Autodesk Fusion 360 part; units mm, degrees
(part 3 of 3)
equation "d3462 = ( wall_z0 + fr_w ) - ( wall_z0 )"
equation "d3464 = fr_t"
equation "d3465 = ( fr_z2 ) - ( wall_z0 )"
equation "d3471 = ( fr_z2 ) - ( wall_z0 )"
equation "d3477 = sk_ref"
equation "d3478 = sk_ref"
equation "d3479 = ( ( ( dl_y1 * ( dl_x2 / dl_l1 ) - ( -( ( ( dl_y2 - dl_y1 ) / dl_l1 * ( -pod_w / 2 ) + dl_x2 / dl_l1 * ( -dl_y1 ) + dl_fo ) ) ) ) / ( -( -( ( dl_y2 - dl_y1 ) / dl_l1 ) ) ) ) ) + sk_ref"
equation "d3480 = ( ( ( ( ( ( dl_y2 - dl_y1 ) / dl_l1 * ( -pod_w / 2 ) + dl_x2 / dl_l1 * ( -dl_y1 ) + dl_fo ) ) * ( ( dl_x3 - dl_x2 ) / dl_l2 ) - ( ( ( ( dl_y3 - dl_y2 ) / dl_l2 * ( -pod_w / 2 + dl_x2 ) + ( dl_x3 - dl_x2 ) / dl_l2 * ( -dl_y2 ) + dl_fo ) ) * ( dl_x2 / dl_l1 ) ) ) / ( ( ( dl_y2 - dl_y1 ) / dl_l1 ) * ( ( dl_x3 - dl_x2 ) / dl_l2 ) - ( ( ( dl_y3 - dl_y2 ) / dl_l2 ) * ( dl_x2 / dl_l1 ) ) ) ) ) + sk_ref"
equation "d3481 = ( ( ( ( ( ( dl_y2 - dl_y1 ) / dl_l1 * ( -pod_w / 2 ) + dl_x2 / dl_l1 * ( -dl_y1 ) + dl_fo + fr_w ) ) * ( ( dl_x3 - dl_x2 ) / dl_l2 ) - ( ( ( ( dl_y3 - dl_y2 ) / dl_l2 * ( -pod_w / 2 + dl_x2 ) + ( dl_x3 - dl_x2 ) / dl_l2 * ( -dl_y2 ) + dl_fo + fr_w ) ) * ( dl_x2 / dl_l1 ) ) ) / ( ( ( dl_y2 - dl_y1 ) / dl_l1 ) * ( ( dl_x3 - dl_x2 ) / dl_l2 ) - ( ( ( dl_y3 - dl_y2 ) / dl_l2 ) * ( dl_x2 / dl_l1 ) ) ) ) ) + sk_ref"
equation "d3482 = ( ( ( ( ( dl_y1 + fr_w ) ) * ( dl_x2 / dl_l1 ) - ( -( ( ( dl_y2 - dl_y1 ) / dl_l1 * ( -pod_w / 2 ) + dl_x2 / dl_l1 * ( -dl_y1 ) + dl_fo + fr_w ) ) ) ) / ( -( -( ( dl_y2 - dl_y1 ) / dl_l1 ) ) ) ) ) + sk_ref"
equation "d3483 = ( ( ( -( ( ( dl_y2 - dl_y1 ) / dl_l1 ) * dl_y1 ) ) / ( -( -( ( dl_y2 - dl_y1 ) / dl_l1 ) ) ) ) ) + sk_ref"
equation "d3484 = ( ( ( ( ( dl_y2 - dl_y1 ) / dl_l1 ) * ( ( ( dl_y3 - dl_y2 ) / dl_l2 * ( -pod_w / 2 + dl_x2 ) + ( dl_x3 - dl_x2 ) / dl_l2 * ( -dl_y2 ) + dl_fo ) ) - ( ( ( dl_y3 - dl_y2 ) / dl_l2 ) * ( ( ( dl_y2 - dl_y1 ) / dl_l1 * ( -pod_w / 2 ) + dl_x2 / dl_l1 * ( -dl_y1 ) + dl_fo ) ) ) ) / ( ( ( dl_y2 - dl_y1 ) / dl_l1 ) * ( ( dl_x3 - dl_x2 ) / dl_l2 ) - ( ( ( dl_y3 - dl_y2 ) / dl_l2 ) * ( dl_x2 / dl_l1 ) ) ) ) ) + sk_ref"
equation "d3485 = ( ( ( ( ( dl_y2 - dl_y1 ) / dl_l1 ) * ( ( ( dl_y3 - dl_y2 ) / dl_l2 * ( -pod_w / 2 + dl_x2 ) + ( dl_x3 - dl_x2 ) / dl_l2 * ( -dl_y2 ) + dl_fo + fr_w ) ) - ( ( ( dl_y3 - dl_y2 ) / dl_l2 ) * ( ( ( dl_y2 - dl_y1 ) / dl_l1 * ( -pod_w / 2 ) + dl_x2 / dl_l1 * ( -dl_y1 ) + dl_fo + fr_w ) ) ) ) / ( ( ( dl_y2 - dl_y1 ) / dl_l1 ) * ( ( dl_x3 - dl_x2 ) / dl_l2 ) - ( ( ( dl_y3 - dl_y2 ) / dl_l2 ) * ( dl_x2 / dl_l1 ) ) ) ) ) + sk_ref"
equation "d3486 = ( ( ( -( ( ( dl_y2 - dl_y1 ) / dl_l1 ) * ( ( dl_y1 + fr_w ) ) ) ) / ( -( -( ( dl_y2 - dl_y1 ) / dl_l1 ) ) ) ) ) + sk_ref"
equation "d3487 = ( fr_z2 ) * ( 1 )"
equation "d3488 = ( fr_z2 + fr_w ) - ( fr_z2 )"
equation "d3490 = fr_t"
equation "d3491 = sk_ref"
equation "d3492 = sk_ref"
equation "d3493 = ( ( ( ( ( ( dl_y2 - dl_y1 ) / dl_l1 * ( -pod_w / 2 ) + dl_x2 / dl_l1 * ( -dl_y1 ) + dl_fo ) ) * ( ( dl_x3 - dl_x2 ) / dl_l2 ) - ( ( ( ( dl_y3 - dl_y2 ) / dl_l2 * ( -pod_w / 2 + dl_x2 ) + ( dl_x3 - dl_x2 ) / dl_l2 * ( -dl_y2 ) + dl_fo ) ) * ( dl_x2 / dl_l1 ) ) ) / ( ( ( dl_y2 - dl_y1 ) / dl_l1 ) * ( ( dl_x3 - dl_x2 ) / dl_l2 ) - ( ( ( dl_y3 - dl_y2 ) / dl_l2 ) * ( dl_x2 / dl_l1 ) ) ) ) ) + sk_ref"
equation "d3494 = ( ( ( -( ( ( -( -pod_w / 2 + dl_w ) + dl_fo + fr_w ) ) * ( ( dl_x3 - dl_x2 ) / dl_l2 ) ) ) / ( -( -( ( dl_x3 - dl_x2 ) / dl_l2 ) ) ) ) ) + sk_ref"
equation "d3495 = ( ( ( ( ( ( dl_y2 - dl_y1 ) / dl_l1 * ( -pod_w / 2 ) + dl_x2 / dl_l1 * ( -dl_y1 ) + dl_fo + fr_w ) ) * ( ( dl_x3 - dl_x2 ) / dl_l2 ) - ( ( ( ( dl_y3 - dl_y2 ) / dl_l2 * ( -pod_w / 2 + dl_x2 ) + ( dl_x3 - dl_x2 ) / dl_l2 * ( -dl_y2 ) + dl_fo + fr_w ) ) * ( dl_x2 / dl_l1 ) ) ) / ( ( ( dl_y2 - dl_y1 ) / dl_l1 ) * ( ( dl_x3 - dl_x2 ) / dl_l2 ) - ( ( ( dl_y3 - dl_y2 ) / dl_l2 ) * ( dl_x2 / dl_l1 ) ) ) ) ) + sk_ref"
equation "d3496 = ( ( ( ( ( dl_y2 - dl_y1 ) / dl_l1 ) * ( ( ( dl_y3 - dl_y2 ) / dl_l2 * ( -pod_w / 2 + dl_x2 ) + ( dl_x3 - dl_x2 ) / dl_l2 * ( -dl_y2 ) + dl_fo ) ) - ( ( ( dl_y3 - dl_y2 ) / dl_l2 ) * ( ( ( dl_y2 - dl_y1 ) / dl_l1 * ( -pod_w / 2 ) + dl_x2 / dl_l1 * ( -dl_y1 ) + dl_fo ) ) ) ) / ( ( ( dl_y2 - dl_y1 ) / dl_l1 ) * ( ( dl_x3 - dl_x2 ) / dl_l2 ) - ( ( ( dl_y3 - dl_y2 ) / dl_l2 ) * ( dl_x2 / dl_l1 ) ) ) ) ) + sk_ref"
equation "d3497 = ( ( ( ( ( dl_y3 - dl_y2 ) / dl_l2 ) * ( ( -( -pod_w / 2 + dl_w ) + dl_fo + fr_w ) ) - ( -( ( ( dl_y3 - dl_y2 ) / dl_l2 * ( -pod_w / 2 + dl_x2 ) + ( dl_x3 - dl_x2 ) / dl_l2 * ( -dl_y2 ) + dl_fo ) ) ) ) / ( -( -( ( dl_x3 - dl_x2 ) / dl_l2 ) ) ) ) ) + sk_ref"
equation "d3498 = ( ( ( ( ( dl_y3 - dl_y2 ) / dl_l2 ) * ( ( -( -pod_w / 2 + dl_w ) + dl_fo + fr_w ) ) - ( -( ( ( dl_y3 - dl_y2 ) / dl_l2 * ( -pod_w / 2 + dl_x2 ) + ( dl_x3 - dl_x2 ) / dl_l2 * ( -dl_y2 ) + dl_fo + fr_w ) ) ) ) / ( -( -( ( dl_x3 - dl_x2 ) / dl_l2 ) ) ) ) ) + sk_ref"
equation "d3499 = ( ( ( ( ( dl_y2 - dl_y1 ) / dl_l1 ) * ( ( ( dl_y3 - dl_y2 ) / dl_l2 * ( -pod_w / 2 + dl_x2 ) + ( dl_x3 - dl_x2 ) / dl_l2 * ( -dl_y2 ) + dl_fo + fr_w ) ) - ( ( ( dl_y3 - dl_y2 ) / dl_l2 ) * ( ( ( dl_y2 - dl_y1 ) / dl_l1 * ( -pod_w / 2 ) + dl_x2 / dl_l1 * ( -dl_y1 ) + dl_fo + fr_w ) ) ) ) / ( ( ( dl_y2 - dl_y1 ) / dl_l1 ) * ( ( dl_x3 - dl_x2 ) / dl_l2 ) - ( ( ( dl_y3 - dl_y2 ) / dl_l2 ) * ( dl_x2 / dl_l1 ) ) ) ) ) + sk_ref"
equation "d3500 = ( fr_z2 ) * ( 1 )"
equation "d3501 = ( fr_z2 + fr_w ) - ( fr_z2 )"
equation "d3503 = fr_t"
equation "d3504 = ( fr_z3 ) - ( wall_z0 )"
equation "d3510 = ( fr_z3 ) - ( wall_z0 )"
equation "d3516 = ( fr_z3 ) - ( fr_z2 )"
equation "d3522 = ( fr_z3 ) - ( fr_z2 )"
equation "d3528 = ( fr_z4 ) - ( wall_z0 )"
equation "d3534 = ( fr_z4 ) - ( wall_z0 )"
equation "d3540 = ( fr_z4 ) - ( fr_z2 )"
equation "d3546 = ( fr_z4 ) - ( fr_z2 )"
equation "d3552 = sk_ref"
equation "d3553 = sk_ref"
equation "d3554 = ( ( hinge_x0 - hinge_clear ) ) + sk_ref"
equation "d3555 = ( ( hinge_x0 - hinge_clear ) - fr_w ) + sk_ref"
equation "d3556 = ( -glass_y - fr_wh / 2 ) + sk_ref"
equation "d3557 = ( -glass_y + fr_wh / 2 ) + sk_ref"
equation "d3558 = ( wall_z0 + fr_w ) * ( 1 )"
equation "d3559 = ( fr_z2 ) - ( wall_z0 + fr_w )"
equation "d3561 = fr_t"
equation "d3562 = sk_ref"
equation "d3563 = sk_ref"
equation "d3564 = ( ( ( -( ( ( -( -pod_w / 2 + dl_w ) + dl_fo + fr_w ) ) * ( ( dl_x3 - dl_x2 ) / dl_l2 ) ) ) / ( -( -( ( dl_x3 - dl_x2 ) / dl_l2 ) ) ) ) ) + sk_ref"
equation "d3565 = ( ( -( ( -( -pod_w / 2 + dl_w ) + dl_fo ) ) ) ) + sk_ref"
equation "d3566 = ( ( -( -( ( ( ( ( dl_y3 - dl_y2 ) / dl_l2 ) * ( ( -( -pod_w / 2 + dl_w ) + dl_fo + fr_w ) ) - ( -( ( ( dl_y3 - dl_y2 ) / dl_l2 * ( -pod_w / 2 + dl_x2 ) + ( dl_x3 - dl_x2 ) / dl_l2 * ( -dl_y2 ) + dl_fo ) ) ) ) / ( -( -( ( dl_x3 - dl_x2 ) / dl_l2 ) ) ) ) ) ) ) ) + sk_ref"
equation "d3567 = ( ( -( -( ( ( ( ( dl_y3 - dl_y2 ) / dl_l2 ) * ( ( -( -pod_w / 2 + dl_w ) + dl_fo + fr_w ) ) - ( -( ( ( dl_y3 - dl_y2 ) / dl_l2 * ( -pod_w / 2 + dl_x2 ) + ( dl_x3 - dl_x2 ) / dl_l2 * ( -dl_y2 ) + dl_fo ) ) ) ) / ( -( -( ( dl_x3 - dl_x2 ) / dl_l2 ) ) ) ) + fr_w ) ) ) ) + sk_ref"
equation "d3568 = ( wall_z0 + fr_w ) * ( 1 )"
equation "d3569 = ( fr_z2 ) - ( wall_z0 + fr_w )"
equation "d3571 = fr_t"
equation "d3572 = sk_ref"
equation "d3573 = sk_ref"
equation "d3574 = ( ( hinge_x0 - hinge_clear ) ) + sk_ref"
equation "d3575 = ( ( hinge_x0 - hinge_clear ) - fr_w ) + sk_ref"
equation "d3576 = ( -glass_y - fr_wh / 2 ) + sk_ref"
equation "d3577 = ( -glass_y + fr_wh / 2 ) + sk_ref"
equation "d3578 = ( fr_z2 + fr_w ) * ( 1 )"
equation "d3579 = ( fr_z3 ) - ( fr_z2 + fr_w )"
equation "d3581 = fr_t"
equation "d3582 = sk_ref"
equation "d3583 = sk_ref"
equation "d3584 = ( ( ( -( ( ( -( -pod_w / 2 + dl_w ) + dl_fo + fr_w ) ) * ( ( dl_x3 - dl_x2 ) / dl_l2 ) ) ) / ( -( -( ( dl_x3 - dl_x2 ) / dl_l2 ) ) ) ) ) + sk_ref"
equation "d3585 = ( ( -( ( -( -pod_w / 2 + dl_w ) + dl_fo ) ) ) ) + sk_ref"
equation "d3586 = ( ( -( -( ( ( ( ( dl_y3 - dl_y2 ) / dl_l2 ) * ( ( -( -pod_w / 2 + dl_w ) + dl_fo + fr_w ) ) - ( -( ( ( dl_y3 - dl_y2 ) / dl_l2 * ( -pod_w / 2 + dl_x2 ) + ( dl_x3 - dl_x2 ) / dl_l2 * ( -dl_y2 ) + dl_fo ) ) ) ) / ( -( -( ( dl_x3 - dl_x2 ) / dl_l2 ) ) ) ) ) ) ) ) + sk_ref"
equation "d3587 = ( ( -( -( ( ( ( ( dl_y3 - dl_y2 ) / dl_l2 ) * ( ( -( -pod_w / 2 + dl_w ) + dl_fo + fr_w ) ) - ( -( ( ( dl_y3 - dl_y2 ) / dl_l2 * ( -pod_w / 2 + dl_x2 ) + ( dl_x3 - dl_x2 ) / dl_l2 * ( -dl_y2 ) + dl_fo ) ) ) ) / ( -( -( ( dl_x3 - dl_x2 ) / dl_l2 ) ) ) ) + fr_w ) ) ) ) + sk_ref"
equation "d3588 = ( fr_z2 + fr_w ) * ( 1 )"
equation "d3589 = ( fr_z3 ) - ( fr_z2 + fr_w )"
equation "d3591 = fr_t"
equation "d3592 = sk_ref"
equation "d3593 = sk_ref"
equation "d3594 = ( ( hinge_x0 - hinge_clear ) ) + sk_ref"
equation "d3595 = ( ( hinge_x0 - hinge_clear ) - fr_w ) + sk_ref"
equation "d3596 = ( -glass_y - fr_wh / 2 ) + sk_ref"
equation "d3597 = ( -glass_y + fr_wh / 2 ) + sk_ref"
equation "d3598 = ( fr_z3 + fr_w ) * ( 1 )"
equation "d3599 = ( fr_z4 ) - ( fr_z3 + fr_w )"
equation "d3601 = fr_t"
equation "d3602 = sk_ref"
equation "d3603 = sk_ref"
equation "d3604 = ( ( ( -( ( ( -( -pod_w / 2 + dl_w ) + dl_fo + fr_w ) ) * ( ( dl_x3 - dl_x2 ) / dl_l2 ) ) ) / ( -( -( ( dl_x3 - dl_x2 ) / dl_l2 ) ) ) ) ) + sk_ref"
equation "d3605 = ( ( -( ( -( -pod_w / 2 + dl_w ) + dl_fo ) ) ) ) + sk_ref"
equation "d3606 = ( ( -( -( ( ( ( ( dl_y3 - dl_y2 ) / dl_l2 ) * ( ( -( -pod_w / 2 + dl_w ) + dl_fo + fr_w ) ) - ( -( ( ( dl_y3 - dl_y2 ) / dl_l2 * ( -pod_w / 2 + dl_x2 ) + ( dl_x3 - dl_x2 ) / dl_l2 * ( -dl_y2 ) + dl_fo ) ) ) ) / ( -( -( ( dl_x3 - dl_x2 ) / dl_l2 ) ) ) ) ) ) ) ) + sk_ref"
equation "d3607 = ( ( -( -( ( ( ( ( dl_y3 - dl_y2 ) / dl_l2 ) * ( ( -( -pod_w / 2 + dl_w ) + dl_fo + fr_w ) ) - ( -( ( ( dl_y3 - dl_y2 ) / dl_l2 * ( -pod_w / 2 + dl_x2 ) + ( dl_x3 - dl_x2 ) / dl_l2 * ( -dl_y2 ) + dl_fo ) ) ) ) / ( -( -( ( dl_x3 - dl_x2 ) / dl_l2 ) ) ) ) + fr_w ) ) ) ) + sk_ref"
equation "d3608 = ( fr_z3 + fr_w ) * ( 1 )"
equation "d3609 = ( fr_z4 ) - ( fr_z3 + fr_w )"
equation "d3611 = fr_t"
equation "d3612 = sk_ref"
equation "d3613 = sk_ref"
equation "d3614 = ( -jf_x ) + sk_ref"
equation "d3615 = ( jf_z1 ) + sk_ref"
equation "d3616 = fr_hole_jf"
equation "d3617 = ( -jf_x ) + sk_ref"
equation "d3618 = ( jf_z2 ) + sk_ref"
equation "d3619 = fr_hole_jf"
equation "d3620 = ( -jf_x ) + sk_ref"
equation "d3621 = ( jf_z3 ) + sk_ref"
equation "d3622 = fr_hole_jf"
equation "d3623 = ( -jf_x ) + sk_ref"
equation "d3624 = ( jf_z4 ) + sk_ref"
equation "d3625 = fr_hole_jf"
equation "d3626 = ( -jf_x ) + sk_ref"
equation "d3627 = ( jf_z5 ) + sk_ref"
equation "d3628 = fr_hole_jf"
equation "d3629 = ( -jf_x ) + sk_ref"
equation "d3630 = ( jf_z6 ) + sk_ref"
equation "d3631 = fr_hole_jf"
equation "d3632 = ( -pod_d / 2 + decor_d - dl_back_t - fr_t - 1 mm ) * ( 1 )"
equation "d3633 = ( -pod_d / 2 + decor_d - dl_back_t + 0.5 mm ) - ( -pod_d / 2 + decor_d - dl_back_t - fr_t - 1 mm )"
equation "d3635 = sk_ref"
equation "d3636 = sk_ref"
equation "d3637 = ( sp_ax ) + sk_ref"
equation "d3638 = ( sp_ay ) + sk_ref"
equation "d3639 = sp_hole"
equation "d3640 = ( wall_z0 - 1 mm ) * ( 1 )"
equation "d3641 = ( wall_z0 + fr_t + 0.5 mm ) - ( wall_z0 - 1 mm )"
equation "d3643 = sk_ref"
equation "d3644 = sk_ref"
equation "d3645 = ( sp_bx - ( ( sp_slot - sp_hole ) / 2 ) * sp_d2x ) + sk_ref"
equation "d3646 = ( sp_by - ( ( sp_slot - sp_hole ) / 2 ) * sp_d2y ) + sk_ref"
equation "d3647 = sp_hole"
equation "d3648 = ( sp_bx + ( ( sp_slot - sp_hole ) / 2 ) * sp_d2x ) + sk_ref"
equation "d3649 = ( sp_by + ( ( sp_slot - sp_hole ) / 2 ) * sp_d2y ) + sk_ref"
equation "d3650 = sp_hole"
equation "d3651 = ( wall_z0 - 1 mm ) * ( 1 )"
equation "d3652 = ( wall_z0 + fr_t + 0.5 mm ) - ( wall_z0 - 1 mm )"
equation "d3654 = sk_ref"
equation "d3655 = sk_ref"
equation "d3656 = ( sp_bx - ( ( sp_slot - sp_hole ) / 2 ) * sp_d2x - ( sp_hole / 2 ) * sp_n2x ) + sk_ref"
equation "d3657 = ( sp_bx + ( ( sp_slot - sp_hole ) / 2 ) * sp_d2x - ( sp_hole / 2 ) * sp_n2x ) + sk_ref"
equation "d3658 = ( sp_bx + ( ( sp_slot - sp_hole ) / 2 ) * sp_d2x + ( sp_hole / 2 ) * sp_n2x ) + sk_ref"
equation "d3659 = ( sp_bx - ( ( sp_slot - sp_hole ) / 2 ) * sp_d2x + ( sp_hole / 2 ) * sp_n2x ) + sk_ref"
equation "d3660 = ( sp_by - ( ( sp_slot - sp_hole ) / 2 ) * sp_d2y - ( sp_hole / 2 ) * sp_n2y ) + sk_ref"
equation "d3661 = ( sp_by + ( ( sp_slot - sp_hole ) / 2 ) * sp_d2y - ( sp_hole / 2 ) * sp_n2y ) + sk_ref"
equation "d3662 = ( sp_by + ( ( sp_slot - sp_hole ) / 2 ) * sp_d2y + ( sp_hole / 2 ) * sp_n2y ) + sk_ref"
equation "d3663 = ( sp_by - ( ( sp_slot - sp_hole ) / 2 ) * sp_d2y + ( sp_hole / 2 ) * sp_n2y ) + sk_ref"
equation "d3664 = ( wall_z0 - 1 mm ) * ( 1 )"
equation "d3665 = ( wall_z0 + fr_t + 0.5 mm ) - ( wall_z0 - 1 mm )"
named bodies: "DL SKIN ACP 3", "DL BACK PLATE AL 2", "HINGE-SIDE STOP 1 (ANGLE, BONDED)", "HINGE-SIDE STOP 2 AND 3 (ANGLE, BONDED)", "HINGE-SIDE STOP 4 (ANGLE, BONDED)", "FRAME-STOP SEAL PS 1515 - HINGE SIDE 1", "FRAME-STOP SEAL PS 1515 - HINGE SIDE 2 AND 3", "FRAME-STOP SEAL PS 1515 - HINGE SIDE 4", "B01 BACK RING BOTTOM 20 x 20 x 1.5", "B02 BACK RING DOOR SIDE 20 x 20 x 1.5", "B03 BACK RING SLOPE UNDER DT 20 x 20 x 1.5", "B04 BACK RING BOLT LINE 60 x 20 x 1.5", "R1D RING BOTTOM - DOOR SIDE 20 x 20 x 1.5", "R1K RING BOTTOM - BACK 20 x 20 x 1.5", "R1O RING BOTTOM - OUTER FACET 20 x 20 x 1.5", "R1F RING BOTTOM - FRONT FACET 20 x 20 x 1.5", "R2O RING BETWEEN HINGES 1 AND 2 - OUTER FACET 20 x 20 x 1.5", "R2F RING BETWEEN HINGES 1 AND 2 - FRONT FACET 20 x 20 x 1.5", "H1 HINGE POST 1 (HINGE H1) 60 x 20 x 1.5", "P1 DOOR-SIDE FRONT POST 1 20 x 20 x 1.5", "H2 HINGE POST 2 (HINGE H2) 60 x 20 x 1.5", "P2 DOOR-SIDE FRONT POST 2 20 x 20 x 1.5", "H3 HINGE POST 3 (HINGE H3) 60 x 20 x 1.5", "P3 DOOR-SIDE FRONT POST 3 20 x 20 x 1.5"
